RPi5 Display Case (Autodesk Fusion 360 design; units mm, degrees)
part number: 2026-10-09-19-00-53-163
part number: 2026-10-09-19-42-08-543
part number: 2026-10-10-03-09-42-760
part number: 2026-10-10-11-31-29-094
Autodesk Fusion 360 part; units mm, degrees
(part 1 of 2)
sketch "Sketch1" plane through (0, 0, 0) normal (0, 0, 1) x (1, 0, 0) in component "Shell"
  line L0 (-58.4, -36.9) -> (101.6, -36.9)
  line L1 (108.4, -30.1) -> (108.4, 66.5)
  line L2 (101.6, 73.3) -> (-58.4, 73.3)
  line L3 (-65.2, 66.5) -> (-65.2, -30.1)
  arc A0 (101.6, -36.9) -> (108.4, -30.1) centre (101.6, -30.1) ccw
  arc A1 (108.4, 66.5) -> (101.6, 73.3) centre (101.6, 66.5) ccw
  arc A2 (-58.4, 73.3) -> (-65.2, 66.5) centre (-58.4, 66.5) ccw
  arc A3 (-65.2, -30.1) -> (-58.4, -36.9) centre (-58.4, -30.1) ccw
  constraint coincident L1.start A0.end
  constraint coincident L2.start A1.end
  constraint coincident L3.start A2.end
  constraint coincident L0.start A3.end
extrude "Extrude1" add sketch "Sketch1" along normal blind 20 from surface at 21.5 makes body 1 in component "Shell"
fillet "Fillet1" radius 2.5 64 edges at (-65.2, 18.2, 41.5) (-63.2083, -34.9083, 41.5) (21.6, -36.9, 41.5) (106.4083, -34.9083, 41.5) (108.4, 18.2, 41.5) (106.4083, 71.3083, 41.5) (21.6, 73.3, 41.5) (-63.2083, 71.3083, 41.5) (-63.2083, 71.3083, 41.5) (-65.2, 18.2, 41.5) (-63.2083, -34.9083, 41.5) (21.6, -36.9, 41.5) (106.4083, -34.9083, 41.5) (108.4, 18.2, 41.5) (106.4083, 71.3083, 41.5) (21.6, 73.3, 41.5) (21.6, 73.3, 41.5) (-63.2083, 71.3083, 41.5) (-65.2, 18.2, 41.5) (-63.2083, -34.9083, 41.5) (21.6, -36.9, 41.5) (106.4083, -34.9083, 41.5) (108.4, 18.2, 41.5) (106.4083, 71.3083, 41.5) (106.4083, 71.3083, 41.5) (21.6, 73.3, 41.5) (-63.2083, 71.3083, 41.5) (-65.2, 18.2, 41.5) (-63.2083, -34.9083, 41.5) (21.6, -36.9, 41.5) (106.4083, -34.9083, 41.5) (108.4, 18.2, 41.5) (108.4, 18.2, 41.5) (106.4083, 71.3083, 41.5) (21.6, 73.3, 41.5) (-63.2083, 71.3083, 41.5) (-65.2, 18.2, 41.5) (-63.2083, -34.9083, 41.5) (21.6, -36.9, 41.5) (106.4083, -34.9083, 41.5) (106.4083, -34.9083, 41.5) (108.4, 18.2, 41.5) (106.4083, 71.3083, 41.5) (21.6, 73.3, 41.5) (-63.2083, 71.3083, 41.5) (-65.2, 18.2, 41.5) (-63.2083, -34.9083, 41.5) (21.6, -36.9, 41.5) (21.6, -36.9, 41.5) (106.4083, -34.9083, 41.5) (108.4, 18.2, 41.5) (106.4083, 71.3083, 41.5) (21.6, 73.3, 41.5) (-63.2083, 71.3083, 41.5) (-65.2, 18.2, 41.5) (-63.2083, -34.9083, 41.5) (-63.2083, -34.9083, 41.5) (21.6, -36.9, 41.5) (106.4083, -34.9083, 41.5) (108.4, 18.2, 41.5) (106.4083, 71.3083, 41.5) (21.6, 73.3, 41.5) (-63.2083, 71.3083, 41.5) (-65.2, 18.2, 41.5) on bodies 1 in component "Shell"
sketch "Sketch2" plane through (0, 0, 0) normal (0, 0, 1) x (1, 0, 0) in component "Shell"
  line L0 (-60.4, -34.1) -> (103.6, -34.1)
  arc A0 (103.6, -34.1) -> (105.6, -32.1) centre (103.6, -32.1) ccw
  line L1 (105.6, -32.1) -> (105.6, 68.5)
  arc A1 (105.6, 68.5) -> (103.6, 70.5) centre (103.6, 68.5) ccw
  line L2 (103.6, 70.5) -> (-60.4, 70.5)
  arc A2 (-60.4, 70.5) -> (-62.4, 68.5) centre (-60.4, 68.5) ccw
  line L3 (-62.4, 68.5) -> (-62.4, -32.1)
  arc A3 (-62.4, -32.1) -> (-60.4, -34.1) centre (-60.4, -32.1) ccw
extrude "Extrude2" cut sketch "Sketch2" along normal blind 17.2 from surface at 21.3 bodies 1 in component "Shell"
sketch "Sketch6" plane through (0, 0, 0) normal (0, 0, 1) x (1, 0, 0) in component "Shell"
  circle A0 centre (-18.4, 56) radius 4.5
  line L0 (-18.65, 56) -> (-18.15, 56)
  arc A1 (-18.15, 56) -> (-16.15, 58) centre (-18.15, 58) ccw
  line L1 (-16.15, 58) -> (-16.15, 62)
  arc A2 (-16.15, 62) -> (-18.15, 64) centre (-18.15, 62) ccw
  line L2 (-18.15, 64) -> (-18.65, 64)
  arc A3 (-18.65, 64) -> (-20.65, 62) centre (-18.65, 62) ccw
  line L3 (-20.65, 62) -> (-20.65, 58)
  arc A4 (-20.65, 58) -> (-18.65, 56) centre (-18.65, 58) ccw
  circle A5 centre (61.6, 56) radius 4.5
  line L4 (61.35, 56) -> (61.85, 56)
  arc A6 (61.85, 56) -> (63.85, 58) centre (61.85, 58) ccw
  line L5 (63.85, 58) -> (63.85, 62)
  arc A7 (63.85, 62) -> (61.85, 64) centre (61.85, 62) ccw
  line L6 (61.85, 64) -> (61.35, 64)
  arc A8 (61.35, 64) -> (59.35, 62) centre (61.35, 62) ccw
  line L7 (59.35, 62) -> (59.35, 58)
  arc A9 (59.35, 58) -> (61.35, 56) centre (61.35, 58) ccw
extrude "Extrude6" cut sketch "Sketch6" along normal blind 3.2 from surface at 38.4 bodies 1 in component "Shell"
sketch "Sketch7" plane through (0, 0, 0) normal (0, 0, 1) x (1, 0, 0) in component "Shell"
  line L0 (14.9, -6.2) -> (15.5, -6.2)
  arc A0 (15.5, -6.2) -> (16.5, -5.2) centre (15.5, -5.2) ccw
  line L1 (16.5, -5.2) -> (16.5, 28.8)
  arc A1 (16.5, 28.8) -> (15.5, 29.8) centre (15.5, 28.8) ccw
  line L2 (15.5, 29.8) -> (14.9, 29.8)
  arc A2 (14.9, 29.8) -> (13.9, 28.8) centre (14.9, 28.8) ccw
  line L3 (13.9, 28.8) -> (13.9, -5.2)
  arc A3 (13.9, -5.2) -> (14.9, -6.2) centre (14.9, -5.2) ccw
  line L4 (20.9, -6.2) -> (21.5, -6.2)
  arc A4 (21.5, -6.2) -> (22.5, -5.2) centre (21.5, -5.2) ccw
  line L5 (22.5, -5.2) -> (22.5, 28.8)
  arc A5 (22.5, 28.8) -> (21.5, 29.8) centre (21.5, 28.8) ccw
  line L6 (21.5, 29.8) -> (20.9, 29.8)
  arc A6 (20.9, 29.8) -> (19.9, 28.8) centre (20.9, 28.8) ccw
  line L7 (19.9, 28.8) -> (19.9, -5.2)
  arc A7 (19.9, -5.2) -> (20.9, -6.2) centre (20.9, -5.2) ccw
  line L8 (26.9, -6.2) -> (27.5, -6.2)
  arc A8 (27.5, -6.2) -> (28.5, -5.2) centre (27.5, -5.2) ccw
  line L9 (28.5, -5.2) -> (28.5, 28.8)
  arc A9 (28.5, 28.8) -> (27.5, 29.8) centre (27.5, 28.8) ccw
  line L10 (27.5, 29.8) -> (26.9, 29.8)
  arc A10 (26.9, 29.8) -> (25.9, 28.8) centre (26.9, 28.8) ccw
  line L11 (25.9, 28.8) -> (25.9, -5.2)
  arc A11 (25.9, -5.2) -> (26.9, -6.2) centre (26.9, -5.2) ccw
  line L12 (32.9, -6.2) -> (33.5, -6.2)
  arc A12 (33.5, -6.2) -> (34.5, -5.2) centre (33.5, -5.2) ccw
  line L13 (34.5, -5.2) -> (34.5, 28.8)
  arc A13 (34.5, 28.8) -> (33.5, 29.8) centre (33.5, 28.8) ccw
  line L14 (33.5, 29.8) -> (32.9, 29.8)
  arc A14 (32.9, 29.8) -> (31.9, 28.8) centre (32.9, 28.8) ccw
  line L15 (31.9, 28.8) -> (31.9, -5.2)
  arc A15 (31.9, -5.2) -> (32.9, -6.2) centre (32.9, -5.2) ccw
  line L16 (38.9, -6.2) -> (39.5, -6.2)
  arc A16 (39.5, -6.2) -> (40.5, -5.2) centre (39.5, -5.2) ccw
  line L17 (40.5, -5.2) -> (40.5, 28.8)
  arc A17 (40.5, 28.8) -> (39.5, 29.8) centre (39.5, 28.8) ccw
  line L18 (39.5, 29.8) -> (38.9, 29.8)
  arc A18 (38.9, 29.8) -> (37.9, 28.8) centre (38.9, 28.8) ccw
  line L19 (37.9, 28.8) -> (37.9, -5.2)
  arc A19 (37.9, -5.2) -> (38.9, -6.2) centre (38.9, -5.2) ccw
  line L20 (44.9, -6.2) -> (45.5, -6.2)
  arc A20 (45.5, -6.2) -> (46.5, -5.2) centre (45.5, -5.2) ccw
  line L21 (46.5, -5.2) -> (46.5, 28.8)
  arc A21 (46.5, 28.8) -> (45.5, 29.8) centre (45.5, 28.8) ccw
  line L22 (45.5, 29.8) -> (44.9, 29.8)
  arc A22 (44.9, 29.8) -> (43.9, 28.8) centre (44.9, 28.8) ccw
  line L23 (43.9, 28.8) -> (43.9, -5.2)
  arc A23 (43.9, -5.2) -> (44.9, -6.2) centre (44.9, -5.2) ccw
  line L24 (50.9, -6.2) -> (51.5, -6.2)
  arc A24 (51.5, -6.2) -> (52.5, -5.2) centre (51.5, -5.2) ccw
  line L25 (52.5, -5.2) -> (52.5, 28.8)
  arc A25 (52.5, 28.8) -> (51.5, 29.8) centre (51.5, 28.8) ccw
  line L26 (51.5, 29.8) -> (50.9, 29.8)
  arc A26 (50.9, 29.8) -> (49.9, 28.8) centre (50.9, 28.8) ccw
  line L27 (49.9, 28.8) -> (49.9, -5.2)
  arc A27 (49.9, -5.2) -> (50.9, -6.2) centre (50.9, -5.2) ccw
extrude "Extrude7" cut sketch "Sketch7" along normal blind 3.2 from surface at 38.4 bodies 1 in component "Shell"
sketch "Sketch8" plane through (0, 0, 0) normal (0, 0, 1) x (1, 0, 0) in component "Shell"
  line L0 (-65.9, 14) -> (-61.5, 14)
  line L1 (-61.5, 14) -> (-61.5, 38)
  line L2 (-61.5, 38) -> (-65.9, 38)
  line L3 (-65.9, 38) -> (-65.9, 14)
extrude "Extrude8" cut sketch "Sketch8" along normal blind 17.6 from surface at 21.4 bodies 1 in component "Shell"
ref_plane "WorkPlane1" through (0, 0, 15.278) normal (0, 0, 1) x (1, 0, 0)
ref_plane "WorkPlane3" through (0, 0, 3.418) normal (0, 0, 1) x (1, 0, 0)
sketch "Fori viti M2.5 (Plane1)" plane through (0, 0, 15.278) normal (0, 0, 1) x (1, 0, 0)
  circle A0 centre (-55.845, -27.8) radius 1.35
  circle A1 centre (99.045, -27.8) radius 1.35
  circle A2 centre (99.045, 64.2) radius 1.35
  circle A3 centre (-55.845, 64.2) radius 1.35
  dimension "d94" = 154.89
  dimension "d95" = 92
  dimension "d96" = 92
  measures "d94" distance of A2.centre A3.centre
  measures "d95" distance of A1.centre A2.centre
  measures "d96" distance of A0.centre A3.centre
sketch "Basi viti shell (Plane1)" plane through (0, 0, 15.278) normal (0, 0, 1) x (1, 0, 0)
  circle A0 centre (-55.845, -27.8) radius 4
  circle A1 centre (-55.845, -27.8) radius 1.35
  circle A2 centre (99.045, -27.8) radius 4
  circle A3 centre (99.045, -27.8) radius 1.35
  circle A4 centre (99.045, 64.2) radius 4
  circle A5 centre (99.045, 64.2) radius 1.35
  circle A6 centre (-55.845, 64.2) radius 4
  circle A7 centre (-55.845, 64.2) radius 1.35
extrude "Extrude9" add sketch "Basi viti shell (Plane1)" along normal blind 23.722 bodies 1 in component "Shell"
sketch "Sketch9" plane through (0, 0, 0) normal (0, 0, 1) x (1, 0, 0) in component "Shell"
  circle A0 centre (-55.845, -27.8) radius 1.35
  circle A1 centre (99.045, -27.8) radius 1.35
  circle A2 centre (99.045, 64.2) radius 1.35
  circle A3 centre (-55.845, 64.2) radius 1.35
extrude "Extrude10" cut sketch "Sketch9" along normal blind 3.6 from surface at 38 bodies 1 in component "Shell"
sketch "Sketch10" plane through (0, 0, 0) normal (0, 0, 1) x (1, 0, 0) in component "Shell"
  circle A0 centre (-55.845, -27.8) radius 2.6
  circle A1 centre (99.045, -27.8) radius 2.6
  circle A2 centre (99.045, 64.2) radius 2.6
  circle A3 centre (-55.845, 64.2) radius 2.6
extrude "Extrude11" cut sketch "Sketch10" along normal blind 19.6 from surface at 22 bodies 1 in component "Shell"
sketch "Griglie speaker" plane through (0, 0, 0) normal (0, 0, 1) x (1, 0, 0) in component "Shell"
  circle A0 centre (-48.55, 43.5) radius 1.2
  circle A1 centre (-44.55, 43.5) radius 1.2
  circle A2 centre (-40.55, 43.5) radius 1.2
  circle A3 centre (-36.55, 43.5) radius 1.2
  circle A4 centre (-32.55, 43.5) radius 1.2
  circle A5 centre (-28.55, 43.5) radius 1.2
  circle A6 centre (-24.55, 43.5) radius 1.2
  circle A7 centre (-20.55, 43.5) radius 1.2
  circle A8 centre (-46.55, 46.96) radius 1.2
  circle A9 centre (-42.55, 46.96) radius 1.2
  circle A10 centre (-38.55, 46.96) radius 1.2
  circle A11 centre (-34.55, 46.96) radius 1.2
  circle A12 centre (-30.55, 46.96) radius 1.2
  circle A13 centre (-26.55, 46.96) radius 1.2
  circle A14 centre (-22.55, 46.96) radius 1.2
  circle A15 centre (-18.55, 46.96) radius 1.2
  circle A16 centre (-48.55, 50.42) radius 1.2
  circle A17 centre (-44.55, 50.42) radius 1.2
  circle A18 centre (-40.55, 50.42) radius 1.2
  circle A19 centre (-36.55, 50.42) radius 1.2
  circle A20 centre (-32.55, 50.42) radius 1.2
  circle A21 centre (-28.55, 50.42) radius 1.2
  circle A22 centre (-46.55, 53.88) radius 1.2
  circle A23 centre (-42.55, 53.88) radius 1.2
  circle A24 centre (-38.55, 53.88) radius 1.2
  circle A25 centre (-34.55, 53.88) radius 1.2
  circle A26 centre (-30.55, 53.88) radius 1.2
  circle A27 centre (-26.55, 53.88) radius 1.2
  circle A28 centre (-48.55, 57.34) radius 1.2
  circle A29 centre (-44.55, 57.34) radius 1.2
  circle A30 centre (-40.55, 57.34) radius 1.2
  circle A31 centre (-36.55, 57.34) radius 1.2
  circle A32 centre (-32.55, 57.34) radius 1.2
  circle A33 centre (-28.55, 57.34) radius 1.2
  circle A34 centre (-46.55, 60.8) radius 1.2
  circle A35 centre (-42.55, 60.8) radius 1.2
  circle A36 centre (-38.55, 60.8) radius 1.2
  circle A37 centre (-34.55, 60.8) radius 1.2
  circle A38 centre (-30.55, 60.8) radius 1.2
  circle A39 centre (-26.55, 60.8) radius 1.2
  circle A40 centre (59.05, 43.5) radius 1.2
  circle A41 centre (63.05, 43.5) radius 1.2
  circle A42 centre (67.05, 43.5) radius 1.2
  circle A43 centre (71.05, 43.5) radius 1.2
  circle A44 centre (75.05, 43.5) radius 1.2
  circle A45 centre (79.05, 43.5) radius 1.2
  circle A46 centre (83.05, 43.5) radius 1.2
  circle A47 centre (87.05, 43.5) radius 1.2
  circle A48 centre (61.05, 46.96) radius 1.2
  circle A49 centre (65.05, 46.96) radius 1.2
  circle A50 centre (69.05, 46.96) radius 1.2
  circle A51 centre (73.05, 46.96) radius 1.2
  circle A52 centre (77.05, 46.96) radius 1.2
  circle A53 centre (81.05, 46.96) radius 1.2
  circle A54 centre (85.05, 46.96) radius 1.2
  circle A55 centre (71.05, 50.42) radius 1.2
  circle A56 centre (75.05, 50.42) radius 1.2
  circle A57 centre (79.05, 50.42) radius 1.2
  circle A58 centre (83.05, 50.42) radius 1.2
  circle A59 centre (87.05, 50.42) radius 1.2
  circle A60 centre (69.05, 53.88) radius 1.2
  circle A61 centre (73.05, 53.88) radius 1.2
  circle A62 centre (77.05, 53.88) radius 1.2
  circle A63 centre (81.05, 53.88) radius 1.2
  circle A64 centre (85.05, 53.88) radius 1.2
  circle A65 centre (71.05, 57.34) radius 1.2
  circle A66 centre (75.05, 57.34) radius 1.2
  circle A67 centre (79.05, 57.34) radius 1.2
  circle A68 centre (83.05, 57.34) radius 1.2
  circle A69 centre (87.05, 57.34) radius 1.2
  circle A70 centre (69.05, 60.8) radius 1.2
  circle A71 centre (73.05, 60.8) radius 1.2
  circle A72 centre (77.05, 60.8) radius 1.2
  circle A73 centre (81.05, 60.8) radius 1.2
  circle A74 centre (85.05, 60.8) radius 1.2
extrude "Extrude12" cut sketch "Griglie speaker" along normal blind 3.2 from surface at 38.4 bodies 1 in component "Shell"
sketch "Fessure aletta" plane through (0, 0, 0) normal (0, 0, 1) x (1, 0, 0) in component "Shell"
  line L0 (8.9, -3.5) -> (9.5, -3.5)
  arc A0 (9.5, -3.5) -> (10.5, -2.5) centre (9.5, -2.5) ccw
  line L1 (10.5, -2.5) -> (10.5, 19.5)
  arc A1 (10.5, 19.5) -> (9.5, 20.5) centre (9.5, 19.5) ccw
  line L2 (9.5, 20.5) -> (8.9, 20.5)
  arc A2 (8.9, 20.5) -> (7.9, 19.5) centre (8.9, 19.5) ccw
  line L3 (7.9, 19.5) -> (7.9, -2.5)
  arc A3 (7.9, -2.5) -> (8.9, -3.5) centre (8.9, -2.5) ccw
  line L4 (2.9, -3.5) -> (3.5, -3.5)
  arc A4 (3.5, -3.5) -> (4.5, -2.5) centre (3.5, -2.5) ccw
  line L5 (4.5, -2.5) -> (4.5, 19.5)
  arc A5 (4.5, 19.5) -> (3.5, 20.5) centre (3.5, 19.5) ccw
  line L6 (3.5, 20.5) -> (2.9, 20.5)
  arc A6 (2.9, 20.5) -> (1.9, 19.5) centre (2.9, 19.5) ccw
  line L7 (1.9, 19.5) -> (1.9, -2.5)
  arc A7 (1.9, -2.5) -> (2.9, -3.5) centre (2.9, -2.5) ccw
  line L8 (-3.1, -3.5) -> (-2.5, -3.5)
  arc A8 (-2.5, -3.5) -> (-1.5, -2.5) centre (-2.5, -2.5) ccw
  line L9 (-1.5, -2.5) -> (-1.5, 19.5)
  arc A9 (-1.5, 19.5) -> (-2.5, 20.5) centre (-2.5, 19.5) ccw
  line L10 (-2.5, 20.5) -> (-3.1, 20.5)
  arc A10 (-3.1, 20.5) -> (-4.1, 19.5) centre (-3.1, 19.5) ccw
  line L11 (-4.1, 19.5) -> (-4.1, -2.5)
  arc A11 (-4.1, -2.5) -> (-3.1, -3.5) centre (-3.1, -2.5) ccw
  line L12 (-9.1, -3.5) -> (-8.5, -3.5)
  arc A12 (-8.5, -3.5) -> (-7.5, -2.5) centre (-8.5, -2.5) ccw
  line L13 (-7.5, -2.5) -> (-7.5, 19.5)
  arc A13 (-7.5, 19.5) -> (-8.5, 20.5) centre (-8.5, 19.5) ccw
  line L14 (-8.5, 20.5) -> (-9.1, 20.5)
  arc A14 (-9.1, 20.5) -> (-10.1, 19.5) centre (-9.1, 19.5) ccw
  line L15 (-10.1, 19.5) -> (-10.1, -2.5)
  arc A15 (-10.1, -2.5) -> (-9.1, -3.5) centre (-9.1, -2.5) ccw
extrude "Extrude13" cut sketch "Fessure aletta" along normal blind 3.2 from surface at 38.4 bodies 1 in component "Shell"
sketch "Fessure bottom" plane through (0, 0, 0) normal (0, 1, 0) x (1, 0, 0) in component "Shell"
  line L0 (-3.1, -23) -> (-2.5, -23)
  arc A0 (-1.5, -24) -> (-2.5, -23) centre (-2.5, -24) ccw
  line L1 (-1.5, -24) -> (-1.5, -34)
  arc A1 (-2.5, -35) -> (-1.5, -34) centre (-2.5, -34) ccw
  line L2 (-2.5, -35) -> (-3.1, -35)
  arc A2 (-4.1, -34) -> (-3.1, -35) centre (-3.1, -34) ccw
  line L3 (-4.1, -34) -> (-4.1, -24)
  arc A3 (-3.1, -23) -> (-4.1, -24) centre (-3.1, -24) ccw
  line L4 (2.9, -23) -> (3.5, -23)
  arc A4 (4.5, -24) -> (3.5, -23) centre (3.5, -24) ccw
  line L5 (4.5, -24) -> (4.5, -34)
  arc A5 (3.5, -35) -> (4.5, -34) centre (3.5, -34) ccw
  line L6 (3.5, -35) -> (2.9, -35)
  arc A6 (1.9, -34) -> (2.9, -35) centre (2.9, -34) ccw
  line L7 (1.9, -34) -> (1.9, -24)
  arc A7 (2.9, -23) -> (1.9, -24) centre (2.9, -24) ccw
  line L8 (8.9, -23) -> (9.5, -23)
  arc A8 (10.5, -24) -> (9.5, -23) centre (9.5, -24) ccw
  line L9 (10.5, -24) -> (10.5, -34)
  arc A9 (9.5, -35) -> (10.5, -34) centre (9.5, -34) ccw
  line L10 (9.5, -35) -> (8.9, -35)
  arc A10 (7.9, -34) -> (8.9, -35) centre (8.9, -34) ccw
  line L11 (7.9, -34) -> (7.9, -24)
  arc A11 (8.9, -23) -> (7.9, -24) centre (8.9, -24) ccw
  line L12 (14.9, -23) -> (15.5, -23)
  arc A12 (16.5, -24) -> (15.5, -23) centre (15.5, -24) ccw
  line L13 (16.5, -24) -> (16.5, -34)
  arc A13 (15.5, -35) -> (16.5, -34) centre (15.5, -34) ccw
  line L14 (15.5, -35) -> (14.9, -35)
  arc A14 (13.9, -34) -> (14.9, -35) centre (14.9, -34) ccw
  line L15 (13.9, -34) -> (13.9, -24)
  arc A15 (14.9, -23) -> (13.9, -24) centre (14.9, -24) ccw
  line L16 (20.9, -23) -> (21.5, -23)
  arc A16 (22.5, -24) -> (21.5, -23) centre (21.5, -24) ccw
  line L17 (22.5, -24) -> (22.5, -34)
  arc A17 (21.5, -35) -> (22.5, -34) centre (21.5, -34) ccw
  line L18 (21.5, -35) -> (20.9, -35)
  arc A18 (19.9, -34) -> (20.9, -35) centre (20.9, -34) ccw
  line L19 (19.9, -34) -> (19.9, -24)
  arc A19 (20.9, -23) -> (19.9, -24) centre (20.9, -24) ccw
  line L20 (26.9, -23) -> (27.5, -23)
  arc A20 (28.5, -24) -> (27.5, -23) centre (27.5, -24) ccw
  line L21 (28.5, -24) -> (28.5, -34)
  arc A21 (27.5, -35) -> (28.5, -34) centre (27.5, -34) ccw
  line L22 (27.5, -35) -> (26.9, -35)
  arc A22 (25.9, -34) -> (26.9, -35) centre (26.9, -34) ccw
  line L23 (25.9, -34) -> (25.9, -24)
  arc A23 (26.9, -23) -> (25.9, -24) centre (26.9, -24) ccw
  line L24 (32.9, -23) -> (33.5, -23)
  arc A24 (34.5, -24) -> (33.5, -23) centre (33.5, -24) ccw
  line L25 (34.5, -24) -> (34.5, -34)
  arc A25 (33.5, -35) -> (34.5, -34) centre (33.5, -34) ccw
  line L26 (33.5, -35) -> (32.9, -35)
  arc A26 (31.9, -34) -> (32.9, -35) centre (32.9, -34) ccw
  line L27 (31.9, -34) -> (31.9, -24)
  arc A27 (32.9, -23) -> (31.9, -24) centre (32.9, -24) ccw
  line L28 (38.9, -23) -> (39.5, -23)
  arc A28 (40.5, -24) -> (39.5, -23) centre (39.5, -24) ccw
  line L29 (40.5, -24) -> (40.5, -34)
  arc A29 (39.5, -35) -> (40.5, -34) centre (39.5, -34) ccw
  line L30 (39.5, -35) -> (38.9, -35)
  arc A30 (37.9, -34) -> (38.9, -35) centre (38.9, -34) ccw
  line L31 (37.9, -34) -> (37.9, -24)
  arc A31 (38.9, -23) -> (37.9, -24) centre (38.9, -24) ccw
  line L32 (44.9, -23) -> (45.5, -23)
  arc A32 (46.5, -24) -> (45.5, -23) centre (45.5, -24) ccw
  line L33 (46.5, -24) -> (46.5, -34)
  arc A33 (45.5, -35) -> (46.5, -34) centre (45.5, -34) ccw
  line L34 (45.5, -35) -> (44.9, -35)
  arc A34 (43.9, -34) -> (44.9, -35) centre (44.9, -34) ccw
  line L35 (43.9, -34) -> (43.9, -24)
  arc A35 (44.9, -23) -> (43.9, -24) centre (44.9, -24) ccw
extrude "Extrude14" cut sketch "Fessure bottom" along normal blind 4.5 from surface at -38 bodies 1 in component "Shell"
sketch "Scavo USB-C" plane through (0, 0, 0) normal (0, 1, 0) x (1, 0, 0) in component "Shell"
  line L0 (43.5, -21.4) -> (57.5, -21.4)
  line L1 (57.5, -21.4) -> (57.5, -25)
  arc A0 (55.5, -27) -> (57.5, -25) centre (55.5, -25) ccw
  line L2 (55.5, -27) -> (45.5, -27)
  arc A1 (43.5, -25) -> (45.5, -27) centre (45.5, -25) ccw
  line L3 (43.5, -25) -> (43.5, -21.4)
extrude "Extrude15" cut sketch "Scavo USB-C" along normal blind 5 from surface at 69 bodies 1 in component "Shell"
fillet "Fillet3" radius 1 4 edges at (95.3157, 62.7535, 15.278) (95.3157, -29.2465, 15.278) (-59.5743, -29.2465, 15.278) (-59.5743, 62.7535, 15.278) on bodies 1 in component "Shell"
fillet "Fillet5" radius 1 4 edges at (-59.5743, 62.7535, 38.5) (-59.5743, -29.2465, 38.5) (95.3157, -29.2465, 38.5) (95.3157, 62.7535, 38.5) on bodies 1 in component "Shell"
sketch "Parete anteriore" plane through (0, 0, 0) normal (0, 0, 1) x (1, 0, 0) in component "Shell"
  line L0 (-58.4, -36.9) -> (101.6, -36.9)
  line L1 (108.4, -30.1) -> (108.4, 66.5)
  line L2 (101.6, 73.3) -> (-58.4, 73.3)
  line L3 (-65.2, 66.5) -> (-65.2, -30.1)
  line L4 (-60.4, -34.1) -> (103.6, -34.1)
  arc A0 (103.6, -34.1) -> (105.6, -32.1) centre (103.6, -32.1) ccw
  line L5 (105.6, -32.1) -> (105.6, 68.5)
  arc A1 (105.6, 68.5) -> (103.6, 70.5) centre (103.6, 68.5) ccw
  line L6 (103.6, 70.5) -> (-60.4, 70.5)
  arc A2 (-60.4, 70.5) -> (-62.4, 68.5) centre (-60.4, 68.5) ccw
  line L7 (-62.4, 68.5) -> (-62.4, -32.1)
  arc A3 (-62.4, -32.1) -> (-60.4, -34.1) centre (-60.4, -32.1) ccw
  arc A4 (101.6, -36.9) -> (108.4, -30.1) centre (101.6, -30.1) ccw
  arc A5 (108.4, 66.5) -> (101.6, 73.3) centre (101.6, 66.5) ccw
  arc A6 (-58.4, 73.3) -> (-65.2, 66.5) centre (-58.4, 66.5) ccw
  arc A7 (-65.2, -30.1) -> (-58.4, -36.9) centre (-58.4, -30.1) ccw
  constraint coincident L1.start A4.end
  constraint coincident L2.start A5.end
  constraint coincident L3.start A6.end
  constraint coincident L0.start A7.end
sketch "Fascia incastro" plane through (0, 0, 0) normal (0, 0, 1) x (1, 0, 0) in component "Shell"
  line L0 (-56.9, -35.3) -> (100.1, -35.3)
  arc A0 (100.1, -35.3) -> (106.8, -28.6) centre (100.1, -28.6) ccw
  line L1 (106.8, -28.6) -> (106.8, 65)
  arc A1 (106.8, 65) -> (100.1, 71.7) centre (100.1, 65) ccw
  line L2 (100.1, 71.7) -> (-56.9, 71.7)
  arc A2 (-56.9, 71.7) -> (-63.6, 65) centre (-56.9, 65) ccw
  line L3 (-63.6, 65) -> (-63.6, -28.6)
  arc A3 (-63.6, -28.6) -> (-56.9, -35.3) centre (-56.9, -28.6) ccw
  line L4 (-60.4, -34.1) -> (103.6, -34.1)
  arc A4 (103.6, -34.1) -> (105.6, -32.1) centre (103.6, -32.1) ccw
  line L5 (105.6, -32.1) -> (105.6, 68.5)
  arc A5 (105.6, 68.5) -> (103.6, 70.5) centre (103.6, 68.5) ccw
  line L6 (103.6, 70.5) -> (-60.4, 70.5)
  arc A6 (-60.4, 70.5) -> (-62.4, 68.5) centre (-60.4, 68.5) ccw
  line L7 (-62.4, 68.5) -> (-62.4, -32.1)
  arc A7 (-62.4, -32.1) -> (-60.4, -34.1) centre (-60.4, -32.1) ccw
sketch "Scavo USB-C basso" plane through (0, 0, 0) normal (0, 1, 0) x (1, 0, 0) in component "Shell"
  arc A0 (45.5, -18.5) -> (43.5, -20.5) centre (45.5, -20.5) ccw
  line L0 (45.5, -18.5) -> (55.5, -18.5)
  arc A1 (57.5, -20.5) -> (55.5, -18.5) centre (55.5, -20.5) ccw
  line L1 (57.5, -20.5) -> (57.5, -24)
  line L2 (57.5, -24) -> (43.5, -24)
  line L3 (43.5, -24) -> (43.5, -20.5)
sketch "Finestra rotellina" plane through (0, 0, 0) normal (1, 0, 0) x (0, 0, -1) in component "Shell"
  line L0 (-9, 5.2) -> (-9, 27.2)
  arc A0 (-9, 27.2) -> (-11, 29.2) centre (-11, 27.2) ccw
  line L1 (-11, 29.2) -> (-15.5, 29.2)
  arc A1 (-15.5, 29.2) -> (-17.5, 27.2) centre (-15.5, 27.2) ccw
  line L2 (-17.5, 27.2) -> (-17.5, 5.2)
  arc A2 (-17.5, 5.2) -> (-15.5, 3.2) centre (-15.5, 5.2) ccw
  line L3 (-15.5, 3.2) -> (-11, 3.2)
  arc A3 (-11, 3.2) -> (-9, 5.2) centre (-11, 5.2) ccw
sketch "Finestre ganci" plane through (0, 0, 0) normal (0, 0, 1) x (1, 0, 0) in component "Shell"
  line L0 (-22.9, -35.5) -> (-13.9, -35.5)
  line L1 (-13.9, -35.5) -> (-13.9, -33.9)
  line L2 (-13.9, -33.9) -> (-22.9, -33.9)
  line L3 (-22.9, -33.9) -> (-22.9, -35.5)
  line L4 (57.1, -35.5) -> (66.1, -35.5)
  line L5 (66.1, -35.5) -> (66.1, -33.9)
  line L6 (66.1, -33.9) -> (57.1, -33.9)
  line L7 (57.1, -33.9) -> (57.1, -35.5)
  line L8 (-22.9, 70.3) -> (-13.9, 70.3)
  line L9 (-13.9, 70.3) -> (-13.9, 71.9)
  line L10 (-13.9, 71.9) -> (-22.9, 71.9)
  line L11 (-22.9, 71.9) -> (-22.9, 70.3)
  line L12 (57.1, 70.3) -> (66.1, 70.3)
  line L13 (66.1, 70.3) -> (66.1, 71.9)
  line L14 (66.1, 71.9) -> (57.1, 71.9)
  line L15 (57.1, 71.9) -> (57.1, 70.3)
  line L16 (-63.8, -16.5) -> (-62.2, -16.5)
  line L17 (-62.2, -16.5) -> (-62.2, -7.5)
  line L18 (-62.2, -7.5) -> (-63.8, -7.5)
  line L19 (-63.8, -7.5) -> (-63.8, -16.5)
  line L20 (105.4, -16.5) -> (107, -16.5)
  line L21 (107, -16.5) -> (107, -7.5)
  line L22 (107, -7.5) -> (105.4, -7.5)
  line L23 (105.4, -7.5) -> (105.4, -16.5)
extrude "Extrude25" add sketch "Parete anteriore" along normal blind 10.15 from surface at 11.4 bodies 1 in component "Shell"
extrude "Extrude26" add sketch "Fascia incastro" along normal blind 7.85 from surface at 3.6 contours L0 A0 A3 L4 A4 A7 | A3 A7 | A0 A4 | A2 L3 A3 A6 L7 A7 | A0 L1 A1 A4 L5 A5 | A2 A6 | A1 A5 | A1 L2 A2 A5 L6 A6 bodies 1 in component "Shell"
extrude "Extrude28" cut sketch "Finestra rotellina" along normal blind 4.6 from surface at 104.7 bodies 1 in component "Shell"
extrude "Extrude29" cut sketch "Finestre ganci" along normal blind 1.9 from surface at 9.4 bodies 1 in component "Shell"
sketch "Nervature torrette display 2" plane through (0, 0, 0) normal (0, 0, 1) x (1, 0, 0) in component "Shell"
  line L0 (-63, -28.8) -> (-59.045, -28.8)
  line L1 (-59.045, -28.8) -> (-59.045, -26.8)
  line L2 (-59.045, -26.8) -> (-63, -26.8)
  line L3 (-63, -26.8) -> (-63, -28.8)
  line L4 (-56.845, -34.7) -> (-54.845, -34.7)
  line L5 (-54.845, -34.7) -> (-54.845, -31)
  line L6 (-54.845, -31) -> (-56.845, -31)
  line L7 (-56.845, -31) -> (-56.845, -34.7)
  line L8 (102.245, -28.8) -> (106.2, -28.8)
  line L9 (106.2, -28.8) -> (106.2, -26.8)
  line L10 (106.2, -26.8) -> (102.245, -26.8)
  line L11 (102.245, -26.8) -> (102.245, -28.8)
  line L12 (98.045, -34.7) -> (100.045, -34.7)
  line L13 (100.045, -34.7) -> (100.045, -31)
  line L14 (100.045, -31) -> (98.045, -31)
  line L15 (98.045, -31) -> (98.045, -34.7)
  line L16 (102.245, 63.2) -> (106.2, 63.2)
  line L17 (106.2, 63.2) -> (106.2, 65.2)
  line L18 (106.2, 65.2) -> (102.245, 65.2)
  line L19 (102.245, 65.2) -> (102.245, 63.2)
  line L20 (98.045, 67.4) -> (100.045, 67.4)
  line L21 (100.045, 67.4) -> (100.045, 71.1)
  line L22 (100.045, 71.1) -> (98.045, 71.1)
  line L23 (98.045, 71.1) -> (98.045, 67.4)
  line L24 (-63, 63.2) -> (-59.045, 63.2)
  line L25 (-59.045, 63.2) -> (-59.045, 65.2)
  line L26 (-59.045, 65.2) -> (-63, 65.2)
  line L27 (-63, 65.2) -> (-63, 63.2)
  line L28 (-56.845, 67.4) -> (-54.845, 67.4)
  line L29 (-54.845, 67.4) -> (-54.845, 71.1)
  line L30 (-54.845, 71.1) -> (-56.845, 71.1)
  line L31 (-56.845, 71.1) -> (-56.845, 67.4)
extrude "Extrude30" add sketch "Nervature torrette display 2" along normal blind 17.1 from surface at 21.5 bodies 1 in component "Shell"
extrude "Extrude31" cut sketch "Scavo USB-C basso" along normal blind 5.5 from surface at 69 bodies 1 in component "Shell"
sketch "Sketch1 (2)" plane through (0, 0, 0) normal (0, 0, 1) x (1, 0, 0) in component "Bezel"
  line L0 (-56.9, -36.6) -> (100.1, -36.6)
  arc A0 (100.1, -36.6) -> (108.1, -28.6) centre (100.1, -28.6) ccw
  line L1 (108.1, -28.6) -> (108.1, 65)
  arc A1 (108.1, 65) -> (100.1, 73) centre (100.1, 65) ccw
  line L2 (100.1, 73) -> (-56.9, 73)
  arc A2 (-56.9, 73) -> (-64.9, 65) centre (-56.9, 65) ccw
  line L3 (-64.9, 65) -> (-64.9, -28.6)
  arc A3 (-64.9, -28.6) -> (-56.9, -36.6) centre (-56.9, -28.6) ccw
extrude "Extrude1'" add sketch "Sketch1 (2)" along normal blind 10.382 from surface at 1.018 separate body makes body 2 in component "Bezel"
fillet "Fillet1'" radius 2 64 edges at (-62.5569, -34.2569, 1.018) (21.6, -36.6, 1.018) (105.7569, -34.2569, 1.018) (108.1, 18.2, 1.018) (105.7569, 70.6569, 1.018) (21.6, 73, 1.018) (-62.5569, 70.6569, 1.018) (-64.9, 18.2, 1.018) (-64.9, 18.2, 1.018) (-62.5569, -34.2569, 1.018) (21.6, -36.6, 1.018) (105.7569, -34.2569, 1.018) (108.1, 18.2, 1.018) (105.7569, 70.6569, 1.018) (21.6, 73, 1.018) (-62.5569, 70.6569, 1.018) (-62.5569, 70.6569, 1.018) (-64.9, 18.2, 1.018) (-62.5569, -34.2569, 1.018) (21.6, -36.6, 1.018) (105.7569, -34.2569, 1.018) (108.1, 18.2, 1.018) (105.7569, 70.6569, 1.018) (21.6, 73, 1.018) (21.6, 73, 1.018) (-62.5569, 70.6569, 1.018) (-64.9, 18.2, 1.018) (-62.5569, -34.2569, 1.018) (21.6, -36.6, 1.018) (105.7569, -34.2569, 1.018) (108.1, 18.2, 1.018) (105.7569, 70.6569, 1.018) (105.7569, 70.6569, 1.018) (21.6, 73, 1.018) (-62.5569, 70.6569, 1.018) (-64.9, 18.2, 1.018) (-62.5569, -34.2569, 1.018) (21.6, -36.6, 1.018) (105.7569, -34.2569, 1.018) (108.1, 18.2, 1.018) (108.1, 18.2, 1.018) (105.7569, 70.6569, 1.018) (21.6, 73, 1.018) (-62.5569, 70.6569, 1.018) (-64.9, 18.2, 1.018) (-62.5569, -34.2569, 1.018) (21.6, -36.6, 1.018) (105.7569, -34.2569, 1.018) (105.7569, -34.2569, 1.018) (108.1, 18.2, 1.018) (105.7569, 70.6569, 1.018) (21.6, 73, 1.018) (-62.5569, 70.6569, 1.018) (-64.9, 18.2, 1.018) (-62.5569, -34.2569, 1.018) (21.6, -36.6, 1.018) (21.6, -36.6, 1.018) (105.7569, -34.2569, 1.018) (108.1, 18.2, 1.018) (105.7569, 70.6569, 1.018) (21.6, 73, 1.018) (-62.5569, 70.6569, 1.018) (-64.9, 18.2, 1.018) (-62.5569, -34.2569, 1.018) on bodies 2 in component "Bezel"
sketch "Interno bordo" plane through (0, 0, 0) normal (0, 0, 1) x (1, 0, 0) in component "Bezel"
  line L0 (-56.9, -35.5) -> (100.1, -35.5)
  arc A0 (100.1, -35.5) -> (107, -28.6) centre (100.1, -28.6) ccw
  line L1 (107, -28.6) -> (107, 65)
  arc A1 (107, 65) -> (100.1, 71.9) centre (100.1, 65) ccw
  line L2 (100.1, 71.9) -> (-56.9, 71.9)
  arc A2 (-56.9, 71.9) -> (-63.8, 65) centre (-56.9, 65) ccw
  line L3 (-63.8, 65) -> (-63.8, -28.6)
  arc A3 (-63.8, -28.6) -> (-56.9, -35.5) centre (-56.9, -28.6) ccw
extrude "Extrude2'" cut sketch "Interno bordo" along normal blind 8.082 from surface at 3.418 bodies 2 in component "Bezel"
sketch "Finestra display" plane through (0, 0, 0) normal (0, 0, 1) x (1, 0, 0) in component "Bezel"
  line L0 (-56.005, -26.76) -> (99.205, -26.76)
  arc A0 (99.205, -26.76) -> (100.705, -25.26) centre (99.205, -25.26) ccw
  line L1 (100.705, -25.26) -> (100.705, 61.66)
  arc A1 (100.705, 61.66) -> (99.205, 63.16) centre (99.205, 61.66) ccw
  line L2 (99.205, 63.16) -> (-56.005, 63.16)
  arc A2 (-56.005, 63.16) -> (-57.505, 61.66) centre (-56.005, 61.66) ccw
  line L3 (-57.505, 61.66) -> (-57.505, -25.26)
  arc A3 (-57.505, -25.26) -> (-56.005, -26.76) centre (-56.005, -25.26) ccw
sketch "Denti ganci" plane through (0, 0, 0) normal (0, 0, 1) x (1, 0, 0) in component "Bezel"
  line L0 (-22.4, -35.6) -> (-14.4, -35.6)
  line L1 (-14.4, -35.6) -> (-14.4, -35)
  line L2 (-14.4, -35) -> (-22.4, -35)
  line L3 (-22.4, -35) -> (-22.4, -35.6)
  line L4 (57.6, -35.6) -> (65.6, -35.6)
  line L5 (65.6, -35.6) -> (65.6, -35)
  line L6 (65.6, -35) -> (57.6, -35)
  line L7 (57.6, -35) -> (57.6, -35.6)
  line L8 (-22.4, 71.4) -> (-14.4, 71.4)
  line L9 (-14.4, 71.4) -> (-14.4, 72)
  line L10 (-14.4, 72) -> (-22.4, 72)
  line L11 (-22.4, 72) -> (-22.4, 71.4)
  line L12 (57.6, 71.4) -> (65.6, 71.4)
  line L13 (65.6, 71.4) -> (65.6, 72)
  line L14 (65.6, 72) -> (57.6, 72)
  line L15 (57.6, 72) -> (57.6, 71.4)
  line L16 (-63.9, -16) -> (-63.3, -16)
  line L17 (-63.3, -16) -> (-63.3, -8)
  line L18 (-63.3, -8) -> (-63.9, -8)
  line L19 (-63.9, -8) -> (-63.9, -16)
  line L20 (106.5, -16) -> (107.1, -16)
  line L21 (107.1, -16) -> (107.1, -8)
  line L22 (107.1, -8) -> (106.5, -8)
  line L23 (106.5, -8) -> (106.5, -16)
extrude "Extrude4" add sketch "Denti ganci" along normal blind 1.5 from surface at 9.6 bodies 2 in component "Bezel"
sketch "Tagli linguette" plane through (0, 0, 0) normal (0, 0, 1) x (1, 0, 0) in component "Bezel"
  line L0 (-24.4, -37) -> (-23.4, -37)
  line L1 (-23.4, -37) -> (-23.4, -35.3)
  line L2 (-23.4, -35.3) -> (-24.4, -35.3)
  line L3 (-24.4, -35.3) -> (-24.4, -37)
  line L4 (-13.4, -37) -> (-12.4, -37)
  line L5 (-12.4, -37) -> (-12.4, -35.3)
  line L6 (-12.4, -35.3) -> (-13.4, -35.3)
  line L7 (-13.4, -35.3) -> (-13.4, -37)
  line L8 (55.6, -37) -> (56.6, -37)
  line L9 (56.6, -37) -> (56.6, -35.3)
  line L10 (56.6, -35.3) -> (55.6, -35.3)
  line L11 (55.6, -35.3) -> (55.6, -37)
  line L12 (66.6, -37) -> (67.6, -37)
  line L13 (67.6, -37) -> (67.6, -35.3)
  line L14 (67.6, -35.3) -> (66.6, -35.3)
  line L15 (66.6, -35.3) -> (66.6, -37)
  line L16 (-24.4, 71.7) -> (-23.4, 71.7)
  line L17 (-23.4, 71.7) -> (-23.4, 73.4)
  line L18 (-23.4, 73.4) -> (-24.4, 73.4)
  line L19 (-24.4, 73.4) -> (-24.4, 71.7)
  line L20 (-13.4, 71.7) -> (-12.4, 71.7)
  line L21 (-12.4, 71.7) -> (-12.4, 73.4)
  line L22 (-12.4, 73.4) -> (-13.4, 73.4)
  line L23 (-13.4, 73.4) -> (-13.4, 71.7)
  line L24 (55.6, 71.7) -> (56.6, 71.7)
  line L25 (56.6, 71.7) -> (56.6, 73.4)
  line L26 (56.6, 73.4) -> (55.6, 73.4)
  line L27 (55.6, 73.4) -> (55.6, 71.7)
  line L28 (66.6, 71.7) -> (67.6, 71.7)
  line L29 (67.6, 71.7) -> (67.6, 73.4)
  line L30 (67.6, 73.4) -> (66.6, 73.4)
  line L31 (66.6, 73.4) -> (66.6, 71.7)
  line L32 (-65.3, -18) -> (-63.6, -18)
  line L33 (-63.6, -18) -> (-63.6, -17)
  line L34 (-63.6, -17) -> (-65.3, -17)
  line L35 (-65.3, -17) -> (-65.3, -18)
  line L36 (-65.3, -7) -> (-63.6, -7)
  line L37 (-63.6, -7) -> (-63.6, -6)
  line L38 (-63.6, -6) -> (-65.3, -6)
  line L39 (-65.3, -6) -> (-65.3, -7)
  line L40 (106.8, -18) -> (108.5, -18)
  line L41 (108.5, -18) -> (108.5, -17)
  line L42 (108.5, -17) -> (106.8, -17)
  line L43 (106.8, -17) -> (106.8, -18)
  line L44 (106.8, -7) -> (108.5, -7)
  line L45 (108.5, -7) -> (108.5, -6)
  line L46 (108.5, -6) -> (106.8, -6)
  line L47 (106.8, -6) -> (106.8, -7)
extrude "Extrude5" cut sketch "Tagli linguette" along normal blind 7.1 from surface at 4.4 bodies 2 in component "Bezel"
chamfer "Chamfer1" distance 0.45 angle 45 6 edges at (106.5, -12, 11.1) (61.6, 71.4, 11.1) (-18.4, 71.4, 11.1) (61.6, -35, 11.1) (-18.4, -35, 11.1) (-63.3, -12, 11.1) tangent chain off on bodies 2 in component "Bezel"
chamfer "Chamfer2" distance 0.25 angle 45 6 edges at (106.5, -12, 9.6) (61.6, 71.4, 9.6) (-18.4, 71.4, 9.6) (61.6, -35, 9.6) (-18.4, -35, 9.6) (-63.3, -12, 9.6) tangent chain off on bodies 2 in component "Bezel"
sketch "Finestra rotellina (2)" plane through (0, 0, 0) normal (1, 0, 0) x (0, 0, -1) in component "Bezel"
  line L0 (-9, 5.2) -> (-9, 27.2)
  arc A0 (-9, 27.2) -> (-11, 29.2) centre (-11, 27.2) ccw
  line L1 (-11, 29.2) -> (-15.5, 29.2)
  arc A1 (-15.5, 29.2) -> (-17.5, 27.2) centre (-15.5, 27.2) ccw
  line L2 (-17.5, 27.2) -> (-17.5, 5.2)
  arc A2 (-17.5, 5.2) -> (-15.5, 3.2) centre (-15.5, 5.2) ccw
  line L3 (-15.5, 3.2) -> (-11, 3.2)
  arc A3 (-11, 3.2) -> (-9, 5.2) centre (-11, 5.2) ccw
extrude "Extrude6'" cut sketch "Finestra rotellina (2)" along normal blind 4.6 from surface at 104.7 bodies 2 in component "Bezel"
sketch "Pulizia esterno fascia" plane through (0, 0, 0) normal (0, 0, 1) x (1, 0, 0) in component "Shell"
  line L0 (-90, -60) -> (130, -60)
  line L1 (130, -60) -> (130, 100)
  line L2 (130, 100) -> (-90, 100)
  line L3 (-90, 100) -> (-90, -60)
  line L4 (-56.9, -35.3) -> (100.1, -35.3)
  arc A0 (100.1, -35.3) -> (106.8, -28.6) centre (100.1, -28.6) ccw
  line L5 (106.8, -28.6) -> (106.8, 65)
  arc A1 (106.8, 65) -> (100.1, 71.7) centre (100.1, 65) ccw
  line L6 (100.1, 71.7) -> (-56.9, 71.7)
  arc A2 (-56.9, 71.7) -> (-63.6, 65) centre (-56.9, 65) ccw
  line L7 (-63.6, 65) -> (-63.6, -28.6)
  arc A3 (-63.6, -28.6) -> (-56.9, -35.3) centre (-56.9, -28.6) ccw
extrude "Extrude32" cut sketch "Pulizia esterno fascia" along normal blind 7.9 from surface at 3.5 bodies 1 in component "Shell"
sketch "Finestre ganci 2" plane through (0, 0, 0) normal (0, 0, 1) x (1, 0, 0) in component "Shell"
  line L0 (-63.8, 43.9) -> (-62.2, 43.9)
  line L1 (-62.2, 43.9) -> (-62.2, 52.9)
  line L2 (-62.2, 52.9) -> (-63.8, 52.9)
  line L3 (-63.8, 52.9) -> (-63.8, 43.9)
  line L4 (105.4, 43.9) -> (107, 43.9)
  line L5 (107, 43.9) -> (107, 52.9)
  line L6 (107, 52.9) -> (105.4, 52.9)
  line L7 (105.4, 52.9) -> (105.4, 43.9)
extrude "Extrude33" cut sketch "Finestre ganci 2" along normal blind 1.9 from surface at 9.4 bodies 1 in component "Shell"
sketch "Denti ganci 2" plane through (0, 0, 0) normal (0, 0, 1) x (1, 0, 0) in component "Bezel"
  line L0 (-63.9, 44.4) -> (-63.3, 44.4)
  line L1 (-63.3, 44.4) -> (-63.3, 52.4)
  line L2 (-63.3, 52.4) -> (-63.9, 52.4)
  line L3 (-63.9, 52.4) -> (-63.9, 44.4)
  line L4 (106.5, 44.4) -> (107.1, 44.4)
  line L5 (107.1, 44.4) -> (107.1, 52.4)
  line L6 (107.1, 52.4) -> (106.5, 52.4)
  line L7 (106.5, 52.4) -> (106.5, 44.4)
extrude "Extrude7'" add sketch "Denti ganci 2" along normal blind 1.5 from surface at 9.6 bodies 2 in component "Bezel"
sketch "Tagli linguette 2" plane through (0, 0, 0) normal (0, 0, 1) x (1, 0, 0) in component "Bezel"
  line L0 (-65.3, 42.4) -> (-63.6, 42.4)
  line L1 (-63.6, 42.4) -> (-63.6, 43.4)
  line L2 (-63.6, 43.4) -> (-65.3, 43.4)
  line L3 (-65.3, 43.4) -> (-65.3, 42.4)
  line L4 (106.8, 42.4) -> (108.5, 42.4)
  line L5 (108.5, 42.4) -> (108.5, 43.4)
  line L6 (108.5, 43.4) -> (106.8, 43.4)
  line L7 (106.8, 43.4) -> (106.8, 42.4)
  line L8 (-65.3, 53.4) -> (-63.6, 53.4)
  line L9 (-63.6, 53.4) -> (-63.6, 54.4)
  line L10 (-63.6, 54.4) -> (-65.3, 54.4)
  line L11 (-65.3, 54.4) -> (-65.3, 53.4)
  line L12 (106.8, 53.4) -> (108.5, 53.4)
  line L13 (108.5, 53.4) -> (108.5, 54.4)
  line L14 (108.5, 54.4) -> (106.8, 54.4)
  line L15 (106.8, 54.4) -> (106.8, 53.4)
extrude "Extrude8'" cut sketch "Tagli linguette 2" along normal blind 7.1 from surface at 4.4 bodies 2 in component "Bezel"
chamfer "Chamfer3" distance 0.45 angle 45 2 edges at (106.5, 48.4, 11.1) (-63.3, 48.4, 11.1) tangent chain off on bodies 2 in component "Bezel"
chamfer "Chamfer4" distance 0.25 angle 45 2 edges at (106.5, 48.4, 9.6) (-63.3, 48.4, 9.6) tangent chain off on bodies 2 in component "Bezel"
sketch "Gradino bottom taglio" plane through (0, 0, 0) normal (0, 0, 1) x (1, 0, 0) in component "Shell"
  line L0 (-90, -60) -> (130, -60)
  line L1 (130, -60) -> (130, -23)
  line L2 (130, -23) -> (-90, -23)
  line L3 (-90, -23) -> (-90, -60)
extrude "Gradino bottom taglio (1)" cut sketch "Gradino bottom taglio" along normal blind 27.5 from surface at 17.5 bodies 1 makes body 3 at (-52.7432, -27.6013, 17.5) makes body 4 at (102.1468, -27.6013, 17.5) in component "Shell"
sketch "Gradino bottom fondo" plane through (0, 0, 0) normal (0, 0, 1) x (1, 0, 0) in component "Shell"
  line L0 (-65.2, -22.5) -> (-65.2, -30.1)
  line L1 (-58.4, -36.9) -> (101.6, -36.9)
  line L2 (108.4, -30.1) -> (108.4, -22.5)
  line L3 (108.4, -22.5) -> (-65.2, -22.5)
  arc A0 (-65.2, -30.1) -> (-58.4, -36.9) centre (-58.4, -30.1) ccw
  arc A1 (101.6, -36.9) -> (108.4, -30.1) centre (101.6, -30.1) ccw
  constraint coincident L1.start A0.end
  constraint coincident L2.start A1.end
extrude "Gradino bottom fondo (1)" add sketch "Gradino bottom fondo" along normal blind 3 from surface at 17.5 bodies 1 in component "Shell"
sketch "Gradino bottom parete" plane through (0, 0, 0) normal (0, 0, 1) x (1, 0, 0) in component "Shell"
  line L0 (-62.2, -23) -> (105.4, -23)
  line L1 (105.4, -23) -> (105.4, -20.5)
  line L2 (105.4, -20.5) -> (-62.2, -20.5)
  line L3 (-62.2, -20.5) -> (-62.2, -23)
extrude "Gradino bottom parete (1)" add sketch "Gradino bottom parete" along normal blind 24 from surface at 17.5 bodies 1 in component "Shell"
extrude "Gradino bottom fessure" cut sketch "Fessure bottom" along normal blind 5 from surface at -24 bodies 1 in component "Shell"
fillet "Raccordo gradino bottom plate" radius 2.5 28 edges at (107, -23, 20.5) (-63.8, -23, 20.5) (21.6, -23, 20.5) (-65.2, -26.55, 20.5) (-63.2083, -34.9083, 20.5) (21.6, -36.9, 20.5) (106.4083, -34.9083, 20.5) (108.4, -26.55, 20.5) (-63.2083, -34.9083, 20.5) (21.6, -36.9, 20.5) (106.4083, -34.9083, 20.5) (108.4, -26.55, 20.5) (-65.2, -26.55, 20.5) (21.6, -36.9, 20.5) (106.4083, -34.9083, 20.5) (108.4, -26.55, 20.5) (-63.2083, -34.9083, 20.5) (-65.2, -26.55, 20.5) (106.4083, -34.9083, 20.5) (108.4, -26.55, 20.5) (21.6, -36.9, 20.5) (-63.2083, -34.9083, 20.5) (-65.2, -26.55, 20.5) (108.4, -26.55, 20.5) (106.4083, -34.9083, 20.5) (21.6, -36.9, 20.5) (-63.2083, -34.9083, 20.5) (-65.2, -26.55, 20.5) on bodies 1 in component "Shell"
sketch "Gradino bottom fori viti" plane through (0, 0, 0) normal (0, 0, 1) x (1, 0, 0) in component "Shell"
  circle A0 centre (-55.85, -27.85) radius 1.35
  circle A1 centre (99.05, -27.85) radius 1.35
extrude "Gradino bottom fori viti (1)" cut sketch "Gradino bottom fori viti" along normal blind 8 from surface at 13 bodies 1 in component "Shell"
sketch "Gradino bottom lamature" plane through (0, 0, 0) normal (0, 0, 1) x (1, 0, 0) in component "Shell"
  circle A0 centre (-55.85, -27.85) radius 2.6
  circle A1 centre (99.05, -27.85) radius 2.6
extrude "Gradino bottom lamature (1)" cut sketch "Gradino bottom lamature" along normal blind 3 from surface at 18 bodies 1 in component "Shell"
combine "Gradino bottom unione torrette" operation add target body 1 tool bodies 3 4 in component "Shell"
sketch "Gradino bottom fori torrette" plane through (0, 0, 0) normal (0, 0, 1) x (1, 0, 0) in component "Shell"
  circle A0 centre (-55.85, -27.85) radius 1.35
  circle A1 centre (99.05, -27.85) radius 1.35
extrude "Gradino bottom fori torrette (1)" cut sketch "Gradino bottom fori torrette" along normal blind 6 from surface at 13 bodies 1 in component "Shell"
sketch "Fascia 1,5" plane through (0, 0, 0) normal (0, 0, 1) x (1, 0, 0) in component "Shell"
  line L0 (-58.4, -34.1) -> (101.6, -34.1)
  arc A0 (101.6, -34.1) -> (105.6, -30.1) centre (101.6, -30.1) ccw
  line L1 (105.6, -30.1) -> (105.6, 66.5)
  arc A1 (105.6, 66.5) -> (101.6, 70.5) centre (101.6, 66.5) ccw
  line L2 (101.6, 70.5) -> (-58.4, 70.5)
  arc A2 (-58.4, 70.5) -> (-62.4, 66.5) centre (-58.4, 66.5) ccw
  line L3 (-62.4, 66.5) -> (-62.4, -30.1)
  arc A3 (-62.4, -30.1) -> (-58.4, -34.1) centre (-58.4, -30.1) ccw
  line L4 (-58.4, -35.6) -> (101.6, -35.6)
  arc A4 (101.6, -35.6) -> (107.1, -30.1) centre (101.6, -30.1) ccw
  line L5 (107.1, -30.1) -> (107.1, 66.5)
  arc A5 (107.1, 66.5) -> (101.6, 72) centre (101.6, 66.5) ccw
  line L6 (101.6, 72) -> (-58.4, 72)
  arc A6 (-58.4, 72) -> (-63.9, 66.5) centre (-58.4, 66.5) ccw
  line L7 (-63.9, 66.5) -> (-63.9, -30.1)
  arc A7 (-63.9, -30.1) -> (-58.4, -35.6) centre (-58.4, -30.1) ccw
extrude "Fascia 1,5 (1)" add sketch "Fascia 1,5" along normal blind 7.85 from surface at 3.6 bodies 1 in component "Shell"
sketch "Finestre ganci 1,5" plane through (0, 0, 0) normal (0, 0, 1) x (1, 0, 0) in component "Shell"
  line L0 (-22.9, -35.8) -> (-13.9, -35.8)
  line L1 (-13.9, -35.8) -> (-13.9, -33.9)
  line L2 (-13.9, -33.9) -> (-22.9, -33.9)
  line L3 (-22.9, -33.9) -> (-22.9, -35.8)
  line L4 (-22.9, 70.3) -> (-13.9, 70.3)
  line L5 (-13.9, 70.3) -> (-13.9, 72.2)
  line L6 (-13.9, 72.2) -> (-22.9, 72.2)
  line L7 (-22.9, 72.2) -> (-22.9, 70.3)
  line L8 (57.1, -35.8) -> (66.1, -35.8)
  line L9 (66.1, -35.8) -> (66.1, -33.9)
  line L10 (66.1, -33.9) -> (57.1, -33.9)
  line L11 (57.1, -33.9) -> (57.1, -35.8)
  line L12 (57.1, 70.3) -> (66.1, 70.3)
  line L13 (66.1, 70.3) -> (66.1, 72.2)
  line L14 (66.1, 72.2) -> (57.1, 72.2)
  line L15 (57.1, 72.2) -> (57.1, 70.3)
  line L16 (-64.1, -16.5) -> (-62.2, -16.5)
  line L17 (-62.2, -16.5) -> (-62.2, -7.5)
  line L18 (-62.2, -7.5) -> (-64.1, -7.5)
  line L19 (-64.1, -7.5) -> (-64.1, -16.5)
  line L20 (105.4, -16.5) -> (107.3, -16.5)
  line L21 (107.3, -16.5) -> (107.3, -7.5)
  line L22 (107.3, -7.5) -> (105.4, -7.5)
  line L23 (105.4, -7.5) -> (105.4, -16.5)
  line L24 (-64.1, 43.9) -> (-62.2, 43.9)
  line L25 (-62.2, 43.9) -> (-62.2, 52.9)
  line L26 (-62.2, 52.9) -> (-64.1, 52.9)
  line L27 (-64.1, 52.9) -> (-64.1, 43.9)
  line L28 (105.4, 43.9) -> (107.3, 43.9)
  line L29 (107.3, 43.9) -> (107.3, 52.9)
  line L30 (107.3, 52.9) -> (105.4, 52.9)
  line L31 (105.4, 52.9) -> (105.4, 43.9)
extrude "Finestre ganci 1,5 (1)" cut sketch "Finestre ganci 1,5" along normal blind 1.9 from surface at 9.4 bodies 1 in component "Shell"
extrude "Finestra rotellina 1,5" cut sketch "Finestra rotellina" along normal blind 4.6 from surface at 104.7 bodies 1 in component "Shell"
sketch "Interno bordo 1,5" plane through (0, 0, 0) normal (0, 0, 1) x (1, 0, 0) in component "Bezel"
  line L0 (-58.4, -35.8) -> (101.6, -35.8)
  arc A0 (101.6, -35.8) -> (107.3, -30.1) centre (101.6, -30.1) ccw
  line L1 (107.3, -30.1) -> (107.3, 66.5)
  arc A1 (107.3, 66.5) -> (101.6, 72.2) centre (101.6, 66.5) ccw
  line L2 (101.6, 72.2) -> (-58.4, 72.2)
  arc A2 (-58.4, 72.2) -> (-64.1, 66.5) centre (-58.4, 66.5) ccw
  line L3 (-64.1, 66.5) -> (-64.1, -30.1)
  arc A3 (-64.1, -30.1) -> (-58.4, -35.8) centre (-58.4, -30.1) ccw
extrude "Interno bordo 1,5 (1)" cut sketch "Interno bordo 1,5" along normal blind 8.082 from surface at 3.418 bodies 2 in component "Bezel"
sketch "Cornice esterno 1,5" plane through (0, 0, 0) normal (0, 0, 1) x (1, 0, 0) in component "Bezel"
  line L0 (-58.4, -33.6) -> (101.6, -33.6)
  arc A0 (101.6, -33.6) -> (105.1, -30.1) centre (101.6, -30.1) ccw
  line L1 (105.1, -30.1) -> (105.1, 66.5)
  arc A1 (105.1, 66.5) -> (101.6, 70) centre (101.6, 66.5) ccw
  line L2 (101.6, 70) -> (-58.4, 70)
  arc A2 (-58.4, 70) -> (-61.9, 66.5) centre (-58.4, 66.5) ccw
  line L3 (-61.9, 66.5) -> (-61.9, -30.1)
  arc A3 (-61.9, -30.1) -> (-58.4, -33.6) centre (-58.4, -30.1) ccw
  line L4 (-58.4, -36.9) -> (101.6, -36.9)
  arc A4 (101.6, -36.9) -> (108.4, -30.1) centre (101.6, -30.1) ccw
  line L5 (108.4, -30.1) -> (108.4, 66.5)
  arc A5 (108.4, 66.5) -> (101.6, 73.3) centre (101.6, 66.5) ccw
  line L6 (101.6, 73.3) -> (-58.4, 73.3)
  arc A6 (-58.4, 73.3) -> (-65.2, 66.5) centre (-58.4, 66.5) ccw
  line L7 (-65.2, 66.5) -> (-65.2, -30.1)
  arc A7 (-65.2, -30.1) -> (-58.4, -36.9) centre (-58.4, -30.1) ccw
extrude "Cornice fronte 1,5" add sketch "Cornice esterno 1,5" along normal blind 2.4 from surface at 1.018 bodies 2 in component "Bezel"
sketch "Cornice bordo 1,5" plane through (0, 0, 0) normal (0, 0, 1) x (1, 0, 0) in component "Bezel"
  line L0 (-58.4, -35.8) -> (101.6, -35.8)
  arc A0 (101.6, -35.8) -> (107.3, -30.1) centre (101.6, -30.1) ccw
  line L1 (107.3, -30.1) -> (107.3, 66.5)
  arc A1 (107.3, 66.5) -> (101.6, 72.2) centre (101.6, 66.5) ccw
  line L2 (101.6, 72.2) -> (-58.4, 72.2)
  arc A2 (-58.4, 72.2) -> (-64.1, 66.5) centre (-58.4, 66.5) ccw
  line L3 (-64.1, 66.5) -> (-64.1, -30.1)
  arc A3 (-64.1, -30.1) -> (-58.4, -35.8) centre (-58.4, -30.1) ccw
  line L4 (-58.4, -36.9) -> (101.6, -36.9)
  arc A4 (101.6, -36.9) -> (108.4, -30.1) centre (101.6, -30.1) ccw
  line L5 (108.4, -30.1) -> (108.4, 66.5)
  arc A5 (108.4, 66.5) -> (101.6, 73.3) centre (101.6, 66.5) ccw
  line L6 (101.6, 73.3) -> (-58.4, 73.3)
  arc A6 (-58.4, 73.3) -> (-65.2, 66.5) centre (-58.4, 66.5) ccw
  line L7 (-65.2, 66.5) -> (-65.2, -30.1)
  arc A7 (-65.2, -30.1) -> (-58.4, -36.9) centre (-58.4, -30.1) ccw
extrude "Cornice bordo 1,5 (1)" add sketch "Cornice bordo 1,5" along normal blind 8.082 from surface at 3.318 bodies 2 in component "Bezel"
fillet "Raccordo fronte 1,5" radius 2 64 edges at (108.4, 18.2, 1.018) (106.4083, 71.3083, 1.018) (21.6, 73.3, 1.018) (-63.2083, 71.3083, 1.018) (-65.2, 18.2, 1.018) (-63.2083, -34.9083, 1.018) (21.6, -36.9, 1.018) (106.4083, -34.9083, 1.018) (106.4083, -34.9083, 1.018) (108.4, 18.2, 1.018) (106.4083, 71.3083, 1.018) (21.6, 73.3, 1.018) (-63.2083, 71.3083, 1.018) (-65.2, 18.2, 1.018) (-63.2083, -34.9083, 1.018) (21.6, -36.9, 1.018) (21.6, -36.9, 1.018) (106.4083, -34.9083, 1.018) (108.4, 18.2, 1.018) (106.4083, 71.3083, 1.018) (21.6, 73.3, 1.018) (-63.2083, 71.3083, 1.018) (-65.2, 18.2, 1.018) (-63.2083, -34.9083, 1.018) (-63.2083, -34.9083, 1.018) (21.6, -36.9, 1.018) (106.4083, -34.9083, 1.018) (108.4, 18.2, 1.018) (106.4083, 71.3083, 1.018) (21.6, 73.3, 1.018) (-63.2083, 71.3083, 1.018) (-65.2, 18.2, 1.018) (-65.2, 18.2, 1.018) (-63.2083, -34.9083, 1.018) (21.6, -36.9, 1.018) (106.4083, -34.9083, 1.018) (108.4, 18.2, 1.018) (106.4083, 71.3083, 1.018) (21.6, 73.3, 1.018) (-63.2083, 71.3083, 1.018) (-63.2083, 71.3083, 1.018) (-65.2, 18.2, 1.018) (-63.2083, -34.9083, 1.018) (21.6, -36.9, 1.018) (106.4083, -34.9083, 1.018) (108.4, 18.2, 1.018) (106.4083, 71.3083, 1.018) (21.6, 73.3, 1.018) (21.6, 73.3, 1.018) (-63.2083, 71.3083, 1.018) (-65.2, 18.2, 1.018) (-63.2083, -34.9083, 1.018) (21.6, -36.9, 1.018) (106.4083, -34.9083, 1.018) (108.4, 18.2, 1.018) (106.4083, 71.3083, 1.018) (106.4083, 71.3083, 1.018) (21.6, 73.3, 1.018) (-63.2083, 71.3083, 1.018) (-65.2, 18.2, 1.018) (-63.2083, -34.9083, 1.018) (21.6, -36.9, 1.018) (106.4083, -34.9083, 1.018) (108.4, 18.2, 1.018) on bodies 2 in component "Bezel"
sketch "Denti ganci 1,5" plane through (0, 0, 0) normal (0, 0, 1) x (1, 0, 0) in component "Bezel"
  line L0 (-22.4, -35.9) -> (-14.4, -35.9)
  line L1 (-14.4, -35.9) -> (-14.4, -35.3)
  line L2 (-14.4, -35.3) -> (-22.4, -35.3)
  line L3 (-22.4, -35.3) -> (-22.4, -35.9)
  line L4 (-22.4, 71.7) -> (-14.4, 71.7)
  line L5 (-14.4, 71.7) -> (-14.4, 72.3)
  line L6 (-14.4, 72.3) -> (-22.4, 72.3)
  line L7 (-22.4, 72.3) -> (-22.4, 71.7)
  line L8 (57.6, -35.9) -> (65.6, -35.9)
  line L9 (65.6, -35.9) -> (65.6, -35.3)
  line L10 (65.6, -35.3) -> (57.6, -35.3)
  line L11 (57.6, -35.3) -> (57.6, -35.9)
  line L12 (57.6, 71.7) -> (65.6, 71.7)
  line L13 (65.6, 71.7) -> (65.6, 72.3)
  line L14 (65.6, 72.3) -> (57.6, 72.3)
  line L15 (57.6, 72.3) -> (57.6, 71.7)
  line L16 (-64.2, -16) -> (-63.6, -16)
  line L17 (-63.6, -16) -> (-63.6, -8)
  line L18 (-63.6, -8) -> (-64.2, -8)
  line L19 (-64.2, -8) -> (-64.2, -16)
  line L20 (106.8, -16) -> (107.4, -16)
  line L21 (107.4, -16) -> (107.4, -8)
  line L22 (107.4, -8) -> (106.8, -8)
  line L23 (106.8, -8) -> (106.8, -16)
  line L24 (-64.2, 44.4) -> (-63.6, 44.4)
  line L25 (-63.6, 44.4) -> (-63.6, 52.4)
  line L26 (-63.6, 52.4) -> (-64.2, 52.4)
  line L27 (-64.2, 52.4) -> (-64.2, 44.4)
  line L28 (106.8, 44.4) -> (107.4, 44.4)
  line L29 (107.4, 44.4) -> (107.4, 52.4)
  line L30 (107.4, 52.4) -> (106.8, 52.4)
  line L31 (106.8, 52.4) -> (106.8, 44.4)
extrude "Denti ganci 1,5 (1)" add sketch "Denti ganci 1,5" along normal blind 1.5 from surface at 9.6 bodies 2 in component "Bezel"